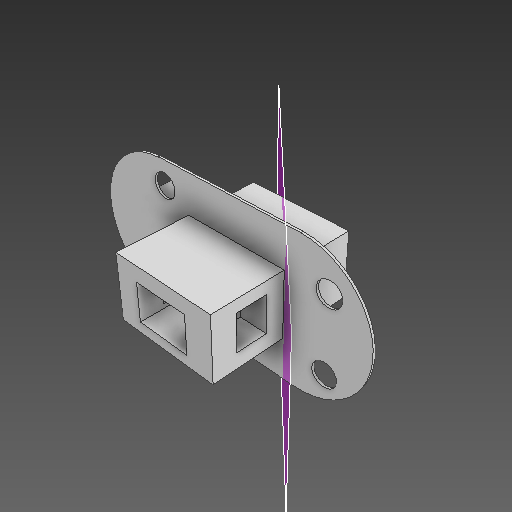
# Autodesk Inventor part: Practice
Saved by Autodesk Inventor 2026.1 (Build 301233020, 233B)
## iProperties
Created: 2026-08-10
Part Number: Practice
Material: Generic
Document SubType Name: Modeling
Designer: YmCris
Density: 1 g/cm^3
Appearance: Default
Author: YmCris
Autodesk Inventor part; units mm, degrees
ref_plane "YZ Plane" through (0, 0, 0) normal (1, 0, 0) x (0, 1, 0)
ref_plane "XZ Plane" through (0, 0, 0) normal (0, 1, 0) x (-1, 0, 0)
ref_plane "XY Plane" through (0, 0, 0) normal (0, 0, 1) x (1, 0, 0)
sketch "Sketch1" plane through (0, 0, 0) normal (0, 1, 0) x (-1, 0, 0)
  point P0 (0, 0)
sketch "Sketch2" plane through (0, 0, 0) normal (0, 0, 1) x (1, 0, 0)
  line L0 (201.6346, -129.7126) -> (-201.6346, -129.7126)
  line L1 (-201.6346, -129.7126) -> (-201.6346, 129.7126)
  line L2 (-201.6346, 129.7126) -> (201.6346, 129.7126)
  line L3 (201.6346, 129.7126) -> (201.6346, -129.7126)
  line L4 (201.6346, -129.7126) -> (-201.6346, 129.7126) construction
  line L5 (-201.6346, -129.7126) -> (201.6346, 129.7126) construction
  line L6 (836.6346, 764.7126) -> (-836.6346, 764.7126)
  line L7 (-836.6346, -764.7126) -> (836.6346, -764.7126)
  line L8 (54.4154, 77.7619) -> (120.8787, 77.7619)
  arc A0 (201.6346, -111.8392) -> (201.6346, 111.8392) centre (269.6859, 0) ccw
  arc A1 (-12.733, 129.7126) -> (-23.6567, -15.2185) centre (741.3352, 0) ccw
  arc A2 (715.6681, -764.7126) -> (715.6681, 764.7126) centre (741.3352, 0) ccw
  line L9 (836.6346, -764.7126) -> (836.6346, -759.1853)
  line L10 (836.6346, 759.1853) -> (836.6346, 764.7126)
  line L11 (-836.6346, 764.7126) -> (-836.6346, 758.7942)
  line L12 (-836.6346, -758.7942) -> (-836.6346, -764.7126)
  arc A3 (-79.5688, 51.1871) -> (-89.0095, 129.7126) centre (-836.6346, 0) ccw
  arc A4 (-836.6346, 758.7942) -> (-836.6346, -758.7942) centre (-836.6346, 0) ccw
  arc A5 (-89.0095, -129.7126) -> (-79.5688, -51.1871) centre (-836.6346, 0) ccw
  circle A6 centre (1065.5539, 363.7345) radius 128.1054
  circle A7 centre (-773.8977, 511.3969) radius 128.1054
  circle A8 centre (1061.335, -433.6425) radius 128.1054
  line L13 (-1090.3171, 0) -> (1189.4404, 0)
  circle A9 centre (-801.2958, -480.2049) radius 128.1054
  point P0 (0, 0)
  point P1 (767.0024, -764.7126)
  point P2 (767.0024, 764.7126)
  dimension "d3" = 25.4
  dimension "d0" = 403.2692
  dimension "d1" = 259.4253
  dimension "d2" = 635
  constraints: 28 end point, 14 point on circle, 11 point on line, 10 centre point, 7 parallel, 3 horizontal, 3 perpendicular, 2 midpoint
  measures "d0" distance of L1.end L2.end
  measures "d1" distance of L2.end L0.start
  measures "d2" distance between parallel lines of L2 L6
extrude "Extrusion1" add sketch "Sketch2" along normal blind 25.4 contours L6 A2 L7 L12 A4 L11
sketch "Sketch3" plane through (0, 0, 25.4) normal (0, 0, 1) x (1, 0, 0)
  line L0 (-481.7426, 349.4121) -> (612.5863, 349.4121)
  line L1 (612.5863, 349.4121) -> (612.5863, -331.5698)
  line L2 (612.5863, -331.5698) -> (-481.7426, -331.5698)
  line L3 (-481.7426, -331.5698) -> (-481.7426, 349.4121)
  point P0 (0, 0)
  dimension "d3" = 25.4
  constraints: 8 end point, 2 parallel, 1 horizontal, 1 perpendicular
extrude "Extrusion2" add sketch "Sketch3" along normal mid plane 1524
ref_plane "Work Plane1" through (612.5863, -331.5698, 25.4) normal (0.7071, 0, -0.7071) x (0, 1, 0)
sketch "Sketch4" plane through (612.5863, -331.5698, 25.4) normal (1, 0, 0) x (0, 0, -1)
  point P0 (25.4, 331.5698)
  dimension "d3" = 25.4
sketch "Sketch5" plane through (0, 0, 787.4) normal (0, 0, 1) x (1, 0, 0)
  line L0 (321.4818, 183.7039) -> (-244.1328, 183.7039)
  line L1 (-244.1328, 183.7039) -> (-244.1328, -217.5441)
  line L2 (-244.1328, -217.5441) -> (321.4818, -217.5441)
  line L3 (321.4818, -217.5441) -> (321.4818, 183.7039)
  point P0 (0, 0)
  dimension "d3" = 25.4
  constraints: 8 end point, 2 parallel, 1 horizontal, 1 perpendicular
extrude "Extrusion3" cut sketch "Sketch5" against normal blind 1524
sketch "Sketch6" plane through (612.5863, -331.5698, 25.4) normal (1, 0, 0) x (0, 0, -1)
  line L0 (-510.5598, 163.2055) -> (-190.6676, 163.2055)
  line L1 (-190.6676, 163.2055) -> (-190.6676, 550.4434)
  line L2 (-190.6676, 550.4434) -> (-510.5598, 550.4434)
  line L3 (-510.5598, 550.4434) -> (-510.5598, 163.2055)
  line L4 (320.0376, 163.2055) -> (639.9298, 163.2055)
  line L5 (639.9298, 163.2055) -> (639.9298, 550.4434)
  line L6 (639.9298, 550.4434) -> (320.0376, 550.4434)
  line L7 (320.0376, 550.4434) -> (320.0376, 163.2055)
  point P0 (25.4, 331.5698)
  dimension "d3" = 25.4
  constraints: 16 end point, 4 parallel, 2 horizontal, 2 perpendicular
extrude "Extrusion4" cut sketch "Sketch6" against normal blind 1524 contours L3 L2 L1 L0
sketch "Sketch7" plane through (-481.7426, -331.5698, 0) normal (-1, 0, 0) x (0, 0, 1)
  line L0 (216.0676, 515.2737) -> (-736.6, 515.2737) projected
  line L1 (-184.3792, 515.2737) -> (-584.3882, 515.2737)
  line L2 (-584.3882, 515.2737) -> (-584.3882, 169.0661)
  line L3 (-584.3882, 169.0661) -> (-184.3792, 169.0661)
  line L4 (-184.3792, 169.0661) -> (-184.3792, 515.2737)
  point P0 (0, 331.5698)
  dimension "d3" = 25.4
  constraints: 8 end point, 2 parallel, 1 horizontal, 1 perpendicular, 1 point on line
extrude "Extrusion5" add sketch "Sketch7" along normal mid plane 1524
body "Solid1"
